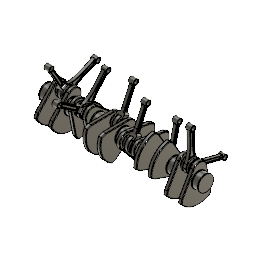
pre exam fork connecting rod v3 (Autodesk Fusion 360 design; units mm, degrees)
Autodesk Fusion 360 part; units mm, degrees
sketch "Sketch1" plane through (0, 0, 0) normal (1, 0, 0) x (0, 1, 0) in component "fork connecting rod v2"
  circle A0 centre (0, 180) radius 10
  circle A1 centre (0, 0) radius 25
  circle A2 centre (0, 0) radius 30
  line L0 (-0.0071, 170) -> (0.0071, 170)
  line L1 (10.2253, 165.3052) -> (10.2253, 67.7414)
  line L2 (-10, 68.0074) -> (-10, 165)
  line L3 (0, 0) -> (0, 30)
  arc A3 (-26.6667, 22.6691) -> (26.7418, 22.5805) centre (0, 0) ccw
  arc A4 (10.2253, 67.7414) -> (26.7418, 22.5805) centre (80.2253, 67.7414) ccw
  arc A5 (-26.6667, 22.6691) -> (-10, 68.0074) centre (-80, 68.0074) ccw
  arc A6 (12.1352, 171.1831) -> (10.2253, 165.3052) centre (20.2253, 165.3052) ccw
  arc A7 (-10, 165) -> (-12, 171) centre (-20, 165) ccw
  line L4 (-12.3703, 49.9456) -> (12.5252, 49.9456)
  arc A8 (-26.6667, 22.6691) -> (26.7418, 22.5805) centre (0, 0) ccw
  circle A9 centre (0, 180) radius 15
  line L5 (-2.5, 160) -> (2.5, 160)
  line L6 (5, 157.5) -> (5, 57.5)
  line L7 (2.5, 55) -> (-2.5, 55)
  line L8 (-5, 57.5) -> (-5, 157.5)
  arc A10 (5, 157.5) -> (2.5, 160) centre (2.5, 157.5) ccw
  arc A11 (-2.5, 160) -> (-5, 157.5) centre (-2.5, 157.5) ccw
  arc A12 (-5, 57.5) -> (-2.5, 55) centre (-2.5, 57.5) ccw
  arc A13 (2.5, 55) -> (5, 57.5) centre (2.5, 57.5) ccw
  dimension "d1" = 180
  dimension "d3" = 20
  dimension "d4" = 70
  dimension "d5" = 50
  dimension "d6" = 60
  dimension "d7" = 70
  dimension "d8" = 70
  dimension "d9" = 10
  dimension "d10" = 10
  dimension "d11" = 70
  dimension "d20" = 30
  dimension "d51" = 2.5
  constraint coincident A1.centre A2.centre
  constraint vertical L3
  constraint concentric A2 A3
  constraint horizontal L0
  constraint vertical L1
  constraint vertical L2
  constraint coincident A0 L0.end
  constraint coincident A0 L0.start
  constraint coincident A2 L3.end
  constraint tangent A3 A4
  constraint tangent L1 A4
  constraint tangent A3 A5
  constraint tangent L2 A5
  constraint tangent L1 A6
  constraint tangent L2 A7
  constraint concentric A2 A8
  constraint coincident A5 L4.start
  constraint coincident A4 L4.end
  constraint concentric A0 A9
  constraint tangent A6 A9
  constraint tangent A7 A9
  constraint horizontal L5
  constraint vertical L6
  constraint horizontal L7
  constraint vertical L8
  constraint tangent L5 A10
  constraint tangent L6 A10
  constraint tangent L5 A11
  constraint tangent L8 A11
  constraint equal A10 A11
  constraint tangent L7 A12
  constraint tangent L8 A12
  constraint equal A10 A12
  constraint tangent L6 A13
  constraint tangent L7 A13
  constraint equal A10 A13
  measures "d1" distance of A1.centre A0.centre
  measures "d3" diameter of A0
  measures "d4" diameter of A3
  measures "d5" diameter of A1
  measures "d6" diameter of A2
  measures "d7" radius of A4
  measures "d8" radius of A5
  measures "d9" radius of A6
  measures "d10" radius of A7
  measures "d11" diameter of A8
  measures "d20" diameter of A9
  measures "d51" radius of A10
extrude "Extrude1" add sketch "Sketch1" along normal mid plane 40 contours A3 A4 A5 L4 A8 makes body 1 in component "fork connecting rod v2"
extrude "Extrude2" add sketch "Sketch1" along normal mid plane 16 contours L1 L2 A4 A5 A6 A7 L4 A9 | L5 L6 L7 L8 A10 A11 A12 A13 bodies 1 in component "fork connecting rod v2"
sketch "Sketch2" plane through (0, 0, 0) normal (0, 1, 0) x (1, 0, 0) in component "fork connecting rod v2"
  line L0 (10, 35) -> (-10, 35)
  line L1 (-10, 35) -> (-10, -35)
  line L2 (-10, -35) -> (10, -35)
  line L3 (10, -35) -> (10, 35)
  line L4 (10, 35) -> (-10, -35) construction
  line L5 (-10, 35) -> (10, -35) construction
  line L6 (-10, -35) -> (10, -35)
  dimension "d16" = 20
  dimension "d17" = 70
  constraint horizontal L0
  constraint perpendicular L0 L1
  constraint parallel L0 L2
  constraint parallel L1 L3
  constraint coincident L4 origin
  constraint coincident L5 origin
  constraint horizontal L6
  measures "d16" distance of L1.end L2.end
  measures "d17" distance of L0.end L1.end
extrude "Extrude3" cut sketch "Sketch2" along normal mid plane 120 bodies 1 in component "fork connecting rod v2"
extrude "Extrude4" add sketch "Sketch1" along normal mid plane 30 separate body contours A9 makes body 2 in component "fork connecting rod v2"
extrude "Extrude5" cut sketch "Sketch2" along normal mid plane 70 bodies 1 in component "fork connecting rod v2"
combine "Combine1" operation add target body 1 tool bodies 2 in component "fork connecting rod v2"
extrude "Extrude6" cut sketch "Sketch1" against normal blind 5 from surface at 8 contours L5 L6 L7 L8 A10 A11 A12 A13 bodies 1 in component "fork connecting rod v2"
extrude "Extrude7" cut sketch "Sketch1" along normal blind 5 from surface at -8 contours L5 L6 L7 L8 A10 A11 A12 A13 bodies 1 in component "fork connecting rod v2"
fillet "Fillet1" radius 10 2 edges at (20, 0.0774, 49.9456) (-20, 0.0774, 49.9456) on bodies 1 in component "fork connecting rod v2"
fillet "Fillet2" radius 2 4 edges at (15, 3.6162, 189.3233) (15, 0, 170) (-15, -3.6162, 189.3233) (-15, 0, 170) on bodies 1 in component "fork connecting rod v2"
fillet "Fillet3" radius 1 2 edges at (15, -13.9849, 174.5758) (-15, -13.9849, 185.4242) on bodies 1 in component "fork connecting rod v2"
fillet "Fillet4" radius 2 8 edges at (-8, 0, 55) (-8, 4.2678, 55.7322) (-8, 5, 107.5) (-8, 4.2678, 159.2678) (-8, 0, 160) (-8, -4.2678, 159.2678) (-8, -5, 107.5) (-8, -4.2678, 55.7322) on bodies 1 in component "fork connecting rod v2"
fillet "Fillet5" radius 2 8 edges at (8, 0, 55) (8, -4.2678, 55.7322) (8, -5, 107.5) (8, -4.2678, 159.2678) (8, 0, 160) (8, 4.2678, 159.2678) (8, 5, 107.5) (8, 4.2678, 55.7322) on bodies 1 in component "fork connecting rod v2"
fillet "Fillet6" radius 1 3 edges at (-10, 22.2148, 28.5651) (-10, -0.0581, -35) (-10, -22.1392, 28.6103) on bodies 1 in component "fork connecting rod v2"
fillet "Fillet7" radius 1 3 edges at (10, -22.1392, 28.6103) (10, -0.0581, -35) (10, 22.2148, 28.5651) on bodies 1 in component "fork connecting rod v2"
fillet "Fillet8" radius 1 7 edges at (9, -12.3703, 49.9456) (17.1928, -13.2605, 46.8925) (20, -20.6369, 30.9125) (20, -0.0581, -35) (20, 20.7242, 30.8684) (17.1902, 13.4014, 46.8953) (9, 12.5252, 49.9456) on bodies 1 in component "fork connecting rod v2"
fillet "Fillet9" radius 1 7 edges at (-9, 12.5252, 49.9456) (-17.1902, 13.4014, 46.8953) (-20, 20.7242, 30.8684) (-20, -0.0581, -35) (-20, -20.6369, 30.9125) (-17.1928, -13.2605, 46.8925) (-9, -12.3703, 49.9456) on bodies 1 in component "fork connecting rod v2"
sketch "Sketch1 (2)" plane through (0, 0, 0) normal (1, 0, 0) x (0, 1, 0) in component "connecting rod v1"
  circle A0 centre (0, 180) radius 10
  circle A1 centre (0, 180) radius 15
  spline S0 degree 5 poles (14.1289, 174.9628) (14.1041, 174.7785) (13.9193, 173.3744) (13.6295, 170.6935) (13.3365, 166.5432) (13.1024, 160.3154) (12.8341, 150.9331) (12.4894, 139.35) (12.1476, 125.79) (11.9802, 110.8045) (12.2053, 95.1605) (13.0319, 79.7016) (14.6038, 65.2216) (16.9502, 52.3483) (19.9026, 41.3752) (23.1406, 32.3006) (25.6757, 26.4449) (27.4128, 22.7625) (28.48, 20.61) (28.9909, 19.6094) knots 0.056559 0.056559 0.056559 0.056559 0.056559 0.056559 0.066667 0.133333 0.2 0.266667 0.333333 0.4 0.466667 0.533333 0.6 0.666667 0.733333 0.8 0.866667 0.933333 1 1 1 1 1 1
  line L0 (15.9, 188.1003) -> (12.3578, 161.8253)
  line L1 (24.602, 28.2048) -> (33.3798, 11.0139)
  spline S1 degree 5 poles (-14.1289, 174.9628) (-14.1041, 174.7785) (-13.9193, 173.3744) (-13.6295, 170.6935) (-13.3365, 166.5432) (-13.1024, 160.3154) (-12.8341, 150.9331) (-12.4894, 139.35) (-12.1476, 125.79) (-11.9802, 110.8045) (-12.2053, 95.1605) (-13.0319, 79.7016) (-14.6038, 65.2216) (-16.9502, 52.3483) (-19.9026, 41.3752) (-23.1406, 32.3006) (-25.6757, 26.4449) (-27.4128, 22.7625) (-28.48, 20.61) (-28.9909, 19.6094) knots 0.056559 0.056559 0.056559 0.056559 0.056559 0.056559 0.066667 0.133333 0.2 0.266667 0.333333 0.4 0.466667 0.533333 0.6 0.666667 0.733333 0.8 0.866667 0.933333 1 1 1 1 1 1
  line L2 (-15.9, 188.1003) -> (-12.3578, 161.8253)
  line L3 (-24.602, 28.2048) -> (-33.3798, 11.0139)
  line L4 (30, 0) -> (35, 0)
  arc A2 (30, 0) -> (-30, 0) centre (0, 0) ccw
  arc A3 (25, 0) -> (-25, 0) centre (0, 0) ccw
  line L5 (35, 0) -> (25, 0)
  line L6 (-25, 0) -> (-40, 0)
  arc A4 (35, 0) -> (28.9909, 19.6094) centre (0, 0) ccw
  arc A5 (-28.9909, 19.6094) -> (-35, 0) centre (0, 0) ccw
  point P0 (-12.9448, 154.7196)
  point P1 (-15.5657, 60.7006)
  point P2 (12.9448, 154.7196)
  point P3 (15.5657, 60.7006)
  dimension "d1_1" = 50
  dimension "d2" = 60
  dimension "d3_1" = 70
  dimension "d4_1" = 20
  dimension "d5_1" = 30
  dimension "d6_1" = 180
  constraint coincident A2.centre A3.centre
  constraint concentric A2 A3
  constraint concentric A2 A4
  constraint concentric A0 A1
  constraint coincident S1.end A4
  constraint coincident A1 S0.start
  constraint midpoint S0.start L0
  constraint midpoint S0.end L1
  constraint coincident A1 S1.start
  constraint midpoint S1.start L2
  constraint midpoint S1.end L3
  constraint horizontal L4
  constraint parallel L4 L5
  constraint coincident A5.end L5
  constraint coincident A2.end L5
  constraint coincident A3.end L5
  constraint collinear L5 L6
  constraint concentric A4 A5
  measures "d1_1" diameter of A3
  measures "d2" diameter of A2
  measures "d3_1" diameter of A4
  measures "d4_1" diameter of A0
  measures "d5_1" diameter of A1
  measures "d6_1" distance of A2.centre A0.centre
extrude "Extrude1'" add sketch "Sketch1 (2)" along normal mid plane 16 separate body contours A1 S0 L1 S1 L3 L4 A2 L5 L6 A4 A5 | L3 A5 | L1 A4 makes body 3 in component "connecting rod v1"
sketch "Sketch2 (2)" plane through (8, 0, 0) normal (1, 0, 0) x (0, 1, 0) in component "connecting rod v1"
  spline S0 degree 5 poles (-14.1289, 174.9628) (-14.1041, 174.7785) (-13.9193, 173.3744) (-13.6295, 170.6935) (-13.3365, 166.5432) (-13.1024, 160.3154) (-12.8341, 150.9331) (-12.4894, 139.35) (-12.1476, 125.79) (-11.9802, 110.8045) (-12.2053, 95.1605) (-13.0319, 79.7016) (-14.6038, 65.2216) (-16.9502, 52.3483) (-19.9026, 41.3752) (-23.1406, 32.3006) (-25.6757, 26.4449) (-27.4128, 22.7625) (-28.48, 20.61) (-28.9909, 19.6094) knots 0.056559 0.056559 0.056559 0.056559 0.056559 0.056559 0.066667 0.133333 0.2 0.266667 0.333333 0.4 0.466667 0.533333 0.6 0.666667 0.733333 0.8 0.866667 0.933333 1 1 1 1 1 1
  arc A0 (35, 0) -> (28.9909, 19.6094) centre (0, 0) ccw
  spline S1 degree 5 poles (28.9909, 19.6094) (28.48, 20.61) (27.4128, 22.7625) (25.6757, 26.4449) (23.1406, 32.3006) (19.9026, 41.3752) (16.9502, 52.3483) (14.6038, 65.2216) (13.0319, 79.7016) (12.2053, 95.1605) (11.9802, 110.8045) (12.1476, 125.79) (12.4894, 139.35) (12.8341, 150.9331) (13.1024, 160.3154) (13.3365, 166.5432) (13.6295, 170.6935) (13.9193, 173.3744) (14.1041, 174.7785) (14.1289, 174.9628) knots -1 -1 -1 -1 -1 -1 -0.933333 -0.866667 -0.8 -0.733333 -0.666667 -0.6 -0.533333 -0.466667 -0.4 -0.333333 -0.266667 -0.2 -0.133333 -0.066667 -0.056559 -0.056559 -0.056559 -0.056559 -0.056559 -0.056559
  arc A1 (-14.1289, 174.9628) -> (14.1289, 174.9628) centre (0, 180) ccw
  arc A2 (14.8211, 38.2274) -> (-14.8211, 38.2274) centre (0, 0) ccw
  spline S2 degree 3 poles (-7.1169, 160.2427) (-6.9895, 156.5185) (-6.8687, 152.3077) (-6.7288, 147.461) (-6.5442, 141.0701) (-6.3256, 133.579) (-6.189, 125.333) (-6.0041, 114.1646) (-5.9891, 101.6466) (-6.5914, 89.4597) (-7.0578, 80.0219) (-7.9058, 70.8124) (-9.1978, 62.4798) (-10.5219, 53.9404) (-12.3163, 46.3351) (-14.3024, 39.8776) (-14.4741, 39.3193) (-14.6471, 38.769) (-14.8211, 38.2274) knots 0.198509 0.198509 0.198509 0.198509 0.285818 0.285818 0.285818 0.400945 0.400945 0.400945 0.556875 0.556875 0.556875 0.677629 0.677629 0.677629 0.80138 0.80138 0.80138 0.81208 0.81208 0.81208 0.81208
  arc A3 (-7.1169, 160.2427) -> (7.1169, 160.2427) centre (0, 180) ccw
  spline S3 degree 3 poles (14.8211, 38.2274) (13.8461, 41.2634) (12.9032, 44.5612) (12.0348, 48.1145) (10.302, 55.2046) (8.8897, 63.3452) (7.9277, 72.1588) (6.6662, 83.7176) (6.168, 96.4115) (6.0882, 108.5641) (6.0272, 117.847) (6.1909, 126.7774) (6.3829, 134.6939) (6.5484, 141.5213) (6.7303, 147.5816) (6.884, 152.7737) (6.964, 155.4763) (7.0385, 157.9524) (7.1169, 160.2427) knots -0.81208 -0.81208 -0.81208 -0.81208 -0.752116 -0.752116 -0.752116 -0.632466 -0.632466 -0.632466 -0.475549 -0.475549 -0.475549 -0.355687 -0.355687 -0.355687 -0.252315 -0.252315 -0.252315 -0.198509 -0.198509 -0.198509 -0.198509
  line L0 (30, 0) -> (35, 0)
  arc A4 (-28.9909, 19.6094) -> (-35, 0) centre (0, 0) ccw
  line L1 (-35, 0) -> (-30, 0)
  arc A5 (30, 0) -> (-30, 0) centre (0, 0) ccw
  constraint concentric A0 A2
  constraint concentric A1 A3
extrude "Extrude2'" add sketch "Sketch1 (2)" along normal mid plane 30 contours A1 L0 L2 | A1 L2 | A1 L0 bodies 3 in component "connecting rod v1"
extrude "Extrude3'" add sketch "Sketch1 (2)" along normal mid plane 30 contours A2 A3 L5 L6 bodies 3 in component "connecting rod v1"
sketch "Sketch3" plane through (0, 0, 0) normal (0, 0, -1) x (1, 0, 0) in component "connecting rod v1"
  line L0 (8, 30) -> (8, 35)
  line L1 (8, 35) -> (-8, 35)
  line L2 (-8, 35) -> (-8, 30)
  line L3 (-8, 30) -> (-15, 30)
  line L4 (-15, 30) -> (-15, 25)
  line L5 (-15, 25) -> (15, 25)
  line L6 (15, 25) -> (15, 30)
  line L7 (15, 30) -> (8, 30)
  circle A0 centre (0, 35) radius 8
  constraint coincident L0.end A0
  constraint tangent L0 A0
  constraint coincident L1.end A0
sketch "Sketch4" plane through (0, 0, 0) normal (0, 0, -1) x (1, 0, 0) in component "connecting rod v1"
  line L0 (-8, 35) -> (-8, 30)
  line L1 (-8, 30) -> (-15, 30)
  line L2 (-15, 30) -> (-15, 25)
  line L3 (-15, 25) -> (15, 25)
  line L4 (15, 25) -> (15, 30)
  line L5 (15, 30) -> (8, 30)
  line L6 (8, 30) -> (8, 35)
  circle A0 centre (0, 35) radius 4
  line L7 (8, 35) -> (-8, 35)
  dimension "d16_1" = 8
  measures "d16_1" diameter of A0
extrude "Extrude6'" cut sketch "Sketch2 (2)" against normal blind 5 contours A2 S2 A3 S3 bodies 3 in component "connecting rod v1"
mirror "Mirror2" about plane through (0, 0, 0) normal (1, 0, 0) of "Extrude6'" in component "connecting rod v1"
fillet "Fillet1'" radius 1 8 edges at (8, 6.181, 101.6063) (8, -6.1802, 101.6017) (8, 0, 41) (8, 0, 159) (-8, 6.181, 101.6063) (-8, 0, 159) (-8, -6.1802, 101.6017) (-8, 0, 41) on bodies 3 in component "connecting rod v1"
fillet "Fillet6'" radius 1 4 edges at (-15, -9.3233, 176.3838) (-15, -13.9849, 185.4242) (15, -9.3233, 183.6162) (15, -13.9849, 174.5758) on bodies 3 in component "connecting rod v1"
fillet "Fillet7'" radius 2 1 edges at (8, 0, 165) on bodies 3 in component "connecting rod v1"
sketch "Sketch1 (3)" plane through (0, 0, 0) normal (1, 0, 0) x (0, 1, 0) in component "connecting rod lid ssg v1"
  line L0 (-35, 0) -> (-25, 0)
  line L1 (25, 0) -> (35, 0)
  arc A0 (-25, 0) -> (25, 0) centre (0, 0) ccw
  arc A1 (-30, 0) -> (30, 0) centre (0, 0) ccw
  arc A2 (-35, 0) -> (35, 0) centre (0, 0) ccw
  dimension "d1_2" = 50
  dimension "d2_1" = 60
  dimension "d3_2" = 70
  constraint coincident A0.centre A1.centre
  constraint concentric A0 A2
  constraint horizontal L0
  constraint parallel L0 L1
  constraint coincident L1 A1.end
  constraint coincident L0 A1.start
  measures "d1_2" diameter of A0
  measures "d2_1" diameter of A1
  measures "d3_2" diameter of A2
extrude "Extrude1''" add sketch "Sketch1 (3)" along normal mid plane 30 separate body contours L0 L1 A0 A1 makes body 4 in component "connecting rod lid ssg v1"
extrude "Extrude2''" add sketch "Sketch1 (3)" along normal mid plane 16 contours L0 L1 A1 A2 bodies 4 in component "connecting rod lid ssg v1"
sketch "Sketch2 (3)" plane through (0, 0, 0) normal (0, 0, 1) x (-1, 0, 0) in component "connecting rod lid ssg v1"
  line L0 (15, 30) -> (8, 30)
  line L1 (8, 30) -> (8, 35)
  line L2 (8, 35) -> (-8, 35)
  line L3 (-8, 35) -> (-8, 30)
  line L4 (-8, 30) -> (-15, 30)
  line L5 (-15, 30) -> (-15, 25)
  line L6 (-15, 25) -> (15, 25)
  line L7 (15, 25) -> (15, 30)
  circle A0 centre (0, 35) radius 8
  constraint coincident L2.end A0
  constraint tangent L3 A0
  constraint coincident L1.end A0
sketch "Sketch3 (2)" plane through (0, 0, 0) normal (0, 0, 1) x (-1, 0, 0) in component "connecting rod lid ssg v1"
  line L0 (-8, 35) -> (-8, 30)
  line L1 (-8, 30) -> (-15, 30)
  line L2 (-15, 30) -> (-15, 25)
  line L3 (-15, 25) -> (15, 25)
  line L4 (15, 25) -> (15, 30)
  line L5 (15, 30) -> (8, 30)
  line L6 (8, 30) -> (8, 35)
  circle A0 centre (0, 35) radius 4
  line L7 (8, 35) -> (-8, 35)
  dimension "d10_2" = 8
  measures "d10_2" diameter of A0
sketch "Sketch1 (4)" plane through (0, 0, 0) normal (1, 0, 0) x (0, 1, 0) in component "Crank v1"
  circle A0 centre (0, 0) radius 40
  line L0 (-37.5877, 13.6808) -> (-81.1936, -106.1253)
  line L1 (-28.0083, 40) -> (134.1892, 40) construction
  line L2 (0, -130) -> (-81.1936, -130)
  line L3 (-81.1936, -106.1253) -> (-81.1936, -130)
  line L4 (37.5877, 13.6808) -> (81.1936, -106.1253)
  line L5 (81.1936, -106.1253) -> (81.1936, -130)
  line L6 (0, -130) -> (81.1936, -130)
  arc A1 (-81.1936, -130) -> (81.1936, -130) centre (0, -40) ccw
  point P0 (0, 20)
  dimension "d1_3" = 80
  dimension "d2_2" = 110
  dimension "d3_3" = 20
  constraint coincident A0.centre origin
  constraint horizontal L1
  constraint tangent A0 L0
  constraint coincident A0 L0.start
  constraint horizontal L2
  constraint perpendicular L2 L3
  constraint coincident A0 A1.centre
  measures "d1_3" diameter of A0
  measures "d2_2" angle of L0 L1
  measures "d3_3" distance of A0.centre P0
sketch "Sketch2 (4)" plane through (0, 0, 0) normal (0, 1, 0) x (1, 0, 0) in component "Crank v1"
  line L0 (-50, 0) -> (-90, 0)
  line L1 (-90, -2) -> (-90, 40)
  line L2 (-90, 40) -> (-50, 40)
  line L3 (-50, 40) -> (-50, -2)
  line L4 (-85, 0) -> (-85, -2)
  line L5 (-55, 0) -> (-55, -2)
  line L6 (-90, -2) -> (-85, -2)
  line L7 (-55, -2) -> (-50, -2)
  line L8 (0, -13.6808) -> (0, 106.1253)
  line L9 (55, -2) -> (50, -2)
  line L10 (90, -2) -> (85, -2)
  line L11 (90, 40) -> (50, 40)
  line L12 (90, -2) -> (90, 40)
  line L13 (85, 0) -> (85, -2)
  line L14 (50, 0) -> (90, 0)
  line L15 (55, 0) -> (55, -2)
  line L16 (50, 40) -> (50, -2)
  line L17 (-90, 40) -> (-70, 40)
  line L18 (-70, 40) -> (-70, 25)
  line L19 (-70, 25) -> (-90, 25)
  line L20 (-90, 25) -> (-90, 40)
  dimension "d5_3" = 50
  dimension "d6_3" = 40
  dimension "d7_3" = 40
  dimension "d9_1" = 2
  dimension "d10_3" = 5
  dimension "d11_2" = 20
  dimension "d12_2" = 15
  constraint horizontal L0
  constraint vertical L1
  constraint horizontal L2
  constraint vertical L3
  constraint horizontal L6
  constraint coincident L0.end L1
  constraint coincident L3.end L6
  constraint coincident L0.start L3
  constraint perpendicular L4 L6
  constraint perpendicular L0 L5
  constraint collinear L6 L7
  constraint coincident L0 L4.start
  constraint coincident L0 L5.start
  constraint equal L6 L7
  constraint symmetric L0.start L8 L14.start
  constraint symmetric L0.end L8 L14.end
  constraint symmetric L1.end L8 L11.start
  constraint symmetric L2.end L8 L11.end
  constraint symmetric L1.start L8 L10.start
  constraint symmetric L3.end L8 L9.end
  constraint symmetric L4.end L8 L10.end
  constraint symmetric L5.end L8 L9.start
  constraint symmetric L4.start L8 L13.start
  constraint symmetric L5.start L8 L15.start
  constraint horizontal L17
  constraint vertical L18
  constraint horizontal L19
  constraint vertical L20
  measures "d5_3" distance of origin L0.start
  measures "d6_3" distance of L0.start L0.end
  measures "d7_3" distance of L0.end L1.end
  measures "d9_1" distance of L4.end L4.start
  measures "d10_3" distance of L1.start L4.end
  measures "d11_2" distance of L1.end L17.end
  measures "d12_2" distance of L1.end L19.end
extrude "Extrude1'''" add sketch "Sketch1 (4)" against normal blind 20 from surface at 50 separate body makes body 5 in component "Crank v1"
mirror "Mirror1" about plane through (0, 0, 0) normal (1, 0, 0) of "Extrude1'''" makes body 6 in component "Crank v1"
revolve "Revolve1" add sketch "Sketch2 (4)" angle 360 about axis through (90, 0, -40) along (-1, 0, 0) separate body contours L0 L3 L5 L7 | L0 L1 L2 L3 L18 L19 | L0 L1 L4 L6 | L9 L14 L15 L16 | L11 L12 L14 L16 | L10 L12 L13 L14 makes body 7 at (-65, -3.9827, -0.1988) makes body 8 at (65, -3.9827, -0.1988) in component "Crank v1"
sketch "Sketch3 (3)" plane through (0, 0, 0) normal (0, 1, 0) x (1, 0, 0) in component "Crank v1"
  line L0 (-50, -13.6808) -> (-50, 106.1253)
  line L1 (-50, 106.1253) -> (-30, 106.1253)
  line L2 (-30, 106.1253) -> (-30, -13.6808)
  line L3 (-30, -13.6808) -> (-50, -13.6808)
  line L4 (50, 106.1253) -> (50, -13.6808)
  line L5 (50, -13.6808) -> (30, -13.6808)
  line L6 (30, -13.6808) -> (30, 106.1253)
  line L7 (30, 106.1253) -> (50, 106.1253)
  line L8 (-30, 0) -> (30, 0)
  line L9 (30, 0) -> (30, -27)
  line L10 (30, -25) -> (-30, -25)
  line L11 (-30, -27) -> (-30, 0)
  line L12 (-25, -25) -> (-25, -27)
  line L13 (25, -25) -> (25, -27)
  line L14 (-30, -27) -> (-25, -27)
  line L15 (25, -27) -> (30, -27)
  dimension "d19_1" = 25
  dimension "d21_2" = 5
  dimension "d22_2" = 5
  dimension "d39" = 60
  constraint horizontal L8
  constraint vertical L9
  constraint horizontal L10
  constraint vertical L11
  constraint coincident L2 L8.start
  constraint horizontal L14
  constraint coincident L9.end L14
  constraint coincident L10.start L9
  constraint coincident L10.end L11
  constraint perpendicular L10 L12
  constraint perpendicular L10 L13
  constraint collinear L14 L15
  constraint coincident L10 L12.start
  constraint coincident L10 L13.start
  measures "d19_1" distance of L8.start L10.end
  measures "d21_2" distance of L9.end L13.end
  measures "d22_2" distance of L11.start L12.end
  measures "d39" distance of L8.start L8.end
revolve "Revolve2" add sketch "Sketch3 (3)" angle 360 about axis through (-30, 0, 0) along (1, 0, 0) separate body contours L2 L6 L8 L9 L10 L11 | L10 L11 L12 L14 | L9 L10 L13 L15 makes body 9 in component "Crank v1"
fillet "Fillet1''" radius 3 24 edges at (30, -59.3906, -46.2223) (30, 0, 40) (30, 59.3906, -46.2223) (50, 59.3906, -46.2223) (50, 0, 40) (50, -59.3906, -46.2223) (30, 81.1936, -118.0627) (50, 81.1936, -118.0627) (30, 0, -161.2122) (50, 0, -161.2122) (30, -81.1936, -118.0627) (50, -81.1936, -118.0627) (-50, 59.3906, -46.2223) (-50, 0, 40) (-50, -59.3906, -46.2223) (-30, -59.3906, -46.2223) (-30, 0, 40) (-30, 59.3906, -46.2223) (-50, 81.1936, -118.0627) (-30, 81.1936, -118.0627) (-50, 0, -161.2122) (-30, 0, -161.2122) (-50, -81.1936, -118.0627) (-30, -81.1936, -118.0627) on bodies 5 6 in component "Crank v1"
combine "Combine1'" operation add target body 5 tool bodies 6 9 in component "Crank v1"
copy_body "Body->Comp1" bodies 5 removing the originals makes body 10 in component "CRANK"
copy_body "CutPasteBodies1" bodies 8 removing the originals makes body 11 in component "CRANK"
copy_body "Body->Comp2" bodies 7 removing the originals makes body 12 in component "ROTOR"
pattern_linear "R-Pattern1" count 6 spacing 140 along (1, 0, 0) of bodies 11 10 makes body 13 at (90, 11.5895, -66.8846) makes body 14 at (250, 38.64, -95.553) makes body 15 at (390, 38.64, -95.553) makes body 16 at (530, 38.64, -95.553) makes body 17 at (670, 38.64, -95.553) makes body 18 at (205, -3.9827, -0.1988) makes body 19 at (345, -3.9827, -0.1988) makes body 20 at (485, -3.9827, -0.1988) makes body 21 at (625, -3.9827, -0.1988) makes body 22 at (765, -3.9827, -0.1988) in component "CRANK"
move_body "Move1" bodies 13 to x (1, 0, 0) y (0, 0.573576, 0.819152) z (0, -0.819152, 0.573576) at (0, -32.7661, -17.0569) in component "CRANK"
move_body "Move2" bodies 14 to x (1, 0, 0) y (0, 0.707107, -0.707107) z (0, 0.707107, 0.707107) at (0, 28.2843, -11.7157) in component "CRANK"
move_body "Move3" bodies 15 to x (1, 0, 0) y (0, 0.087156, 0.996195) z (0, -0.996195, 0.087156) at (0, -39.8478, -36.5138) in component "CRANK"
move_body "Move4" bodies 16 to x (1, 0, 0) y (0, -0.258819, -0.965926) z (0, 0.965926, -0.258819) at (0, 38.637, -50.3528) in component "CRANK"
move_body "Move5" bodies 17 to x (1, 0, 0) y (0, 0.965926, 0.258819) z (0, -0.258819, 0.965926) at (0, -10.3528, -1.363) in component "CRANK"
pattern_linear "R-Pattern1'" count 6 spacing 140 along (1, 0, 0) of bodies 1 makes body 23 at (142.6667, -13.064, 172.629) makes body 24 at (282.6667, -13.064, 172.629) makes body 25 at (422.6667, -13.064, 172.629) makes body 26 at (562.6667, -13.064, 172.629) makes body 27 at (702.6667, -13.064, 172.629) in component "fork connecting rod v2"
pattern_linear "R-Pattern1''" count 6 spacing 140 along (1, 0, 0) of bodies 3 makes body 28 at (145, -21.3323, 13.0359) makes body 29 at (285, -21.3323, 13.0359) makes body 30 at (425, -21.3323, 13.0359) makes body 31 at (565, -21.3323, 13.0359) makes body 32 at (705, -21.3323, 13.0359) in component "connecting rod v1"
pattern_linear "R-Pattern1'''" count 6 spacing 140 along (1, 0, 0) of bodies 4 makes body 33 at (135, 13.5637, -21.0006) makes body 34 at (275, 13.5637, -21.0006) makes body 35 at (415, 13.5637, -21.0006) makes body 36 at (555, 13.5637, -21.0006) makes body 37 at (695, 13.5637, -21.0006) in component "connecting rod lid ssg v1"
copy_body "Body->Comp1'" bodies 1 removing the originals makes body 38 in component "Component"
copy_body "Body->Comp2'" bodies 23 removing the originals makes body 39 in component "Component'"
copy_body "Body->Comp3" bodies 24 removing the originals makes body 40 in component "Component''"
copy_body "Body->Comp4" bodies 25 removing the originals makes body 41 in component "Component'''"
copy_body "Body->Comp5" bodies 26 removing the originals makes body 42 in component "Component''''"
copy_body "Body->Comp6" bodies 27 removing the originals makes body 43 in component "Component'''''"
copy_body "Body->Comp1''" bodies 3 removing the originals makes body 44 in component "Component''''''"
copy_body "Body->Comp2''" bodies 28 removing the originals makes body 45 in component "Component'''''''"
copy_body "Body->Comp3'" bodies 29 removing the originals makes body 46 in component "Component''''''''"
copy_body "Body->Comp4'" bodies 30 removing the originals makes body 47 in component "Component'''''''''"
copy_body "Body->Comp5'" bodies 31 removing the originals makes body 48 in component "Component''''''''''"
copy_body "Body->Comp6'" bodies 32 removing the originals makes body 49 in component "Component'''''''''''"
copy_body "Body->Comp1'''" bodies 4 removing the originals makes body 50 in component "Component''''''''''''"
copy_body "Body->Comp2'''" bodies 33 removing the originals makes body 51 in component "Component'''''''''''''"
copy_body "Body->Comp3''" bodies 34 removing the originals makes body 52 in component "Component''''''''''''''"
copy_body "Body->Comp4''" bodies 35 removing the originals makes body 53 in component "Component'''''''''''''''"
copy_body "Body->Comp5''" bodies 36 removing the originals makes body 54 in component "Component''''''''''''''''"
copy_body "Body->Comp6''" bodies 37 removing the originals makes body 55 in component "Component'''''''''''''''''"
component "fork connecting rod v2" placed x (1, 0, 0) y (0, 0.998603, 0.052839) z (0, -0.052839, 0.998603) at (210, 421.9592, -6.5666)
component "connecting rod v1" placed x (1, 0, 0) y (0, -0.070637, -0.997502) z (0, 0.997502, -0.070637) at (210, 421.9592, -6.5666)
component "connecting rod lid ssg v1" placed x (1, 0, 0) y (0, -0.070637, -0.997502) z (0, 0.997502, -0.070637) at (210, 421.9592, -6.5666)
component "Crank v1" placed x (1, 0, 0) y (0, 1, 0) z (0, 0, 1) at (210, 400, 0)
component "Component" placed x (1, 0, 0) y (0, 1, 0) z (0, 0, 1) at (0, 0, 0) in component "fork connecting rod v2"
component "Component'" placed x (1, 0, 0) y (0, 0.80566, -0.592379) z (0, 0.592379, 0.80566) at (0, -36.5025, 5.6678) in component "fork connecting rod v2"
component "Component''" placed x (1, 0, 0) y (0, 0.80566, -0.592379) z (0, 0.592379, 0.80566) at (0, 15.8474, -26.1939) in component "fork connecting rod v2"
component "Component'''" placed x (1, 0, 0) y (0, 0.80566, -0.592379) z (0, 0.592379, 0.80566) at (0, -53.7338, -5.8127) in component "fork connecting rod v2"
component "Component''''" placed x (1, 0, 0) y (0, 0.80566, -0.592379) z (0, 0.592379, 0.80566) at (0, 1.3004, -63.455) in component "fork connecting rod v2"
component "Component'''''" placed x (1, 0, 0) y (0, 0.80566, -0.592379) z (0, 0.592379, 0.80566) at (0, -9.1482, 5.0347) in component "fork connecting rod v2"
component "Component''''''" placed x (1, 0, 0) y (0, 1, 0) z (0, 0, 1) at (0, 0, 0) in component "connecting rod v1"
component "Component'''''''" placed x (1, 0, 0) y (0, 0.80566, -0.592379) z (0, 0.592379, 0.80566) at (0, -1.1258, -36.9228) in component "connecting rod v1"
component "Component''''''''" placed x (1, 0, 0) y (0, 0.80566, -0.592379) z (0, 0.592379, 0.80566) at (0, 24.0411, 18.9548) in component "connecting rod v1"
component "Component'''''''''" placed x (1, 0, 0) y (0, 0.80566, -0.592379) z (0, 0.592379, 0.80566) at (0, 12.3909, -52.6077) in component "connecting rod v1"
component "Component''''''''''" placed x (1, 0, 0) y (0, 0.80566, -0.592379) z (0, 0.592379, 0.80566) at (0, 62.811, 9.1111) in component "connecting rod v1"
component "Component'''''''''''" placed x (1, 0, 0) y (0, 0.80566, -0.592379) z (0, 0.592379, 0.80566) at (0, -3.8688, -9.699) in component "connecting rod v1"
component "Component''''''''''''" placed x (1, 0, 0) y (0, 1, 0) z (0, 0, 1) at (0, 0, 0) in component "connecting rod lid ssg v1"
component "Component'''''''''''''" placed x (1, 0, 0) y (0, 0.80566, -0.592379) z (0, 0.592379, 0.80566) at (0, -1.1258, -36.9228) in component "connecting rod lid ssg v1"
component "Component''''''''''''''" placed x (1, 0, 0) y (0, 0.80566, -0.592379) z (0, 0.592379, 0.80566) at (0, 24.0411, 18.9548) in component "connecting rod lid ssg v1"
component "Component'''''''''''''''" placed x (1, 0, 0) y (0, 0.80566, -0.592379) z (0, 0.592379, 0.80566) at (0, 12.3909, -52.6077) in component "connecting rod lid ssg v1"
component "Component''''''''''''''''" placed x (1, 0, 0) y (0, 0.80566, -0.592379) z (0, 0.592379, 0.80566) at (0, 62.811, 9.1111) in component "connecting rod lid ssg v1"
component "Component'''''''''''''''''" placed x (1, 0, 0) y (0, 0.80566, -0.592379) z (0, 0.592379, 0.80566) at (0, -3.8688, -9.699) in component "connecting rod lid ssg v1"
component "CRANK" placed x (1, 0, 0) y (0, 0.835835, -0.548981) z (0, 0.548981, 0.835835) at (0, 21.9592, -6.5666) in component "Crank v1"
component "ROTOR" placed x (1, 0, 0) y (0, 1, 0) z (0, 0, 1) at (0, 0, 0) in component "Crank v1"
